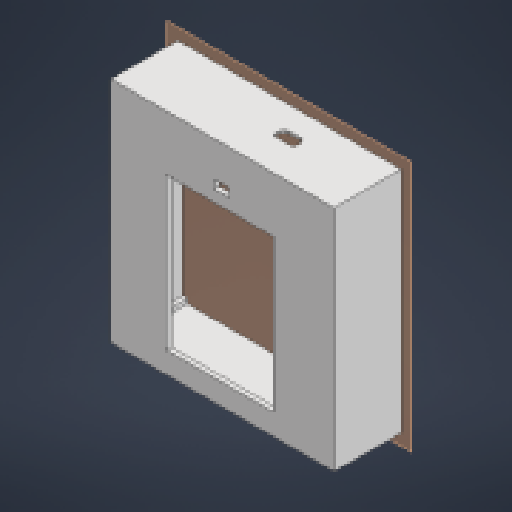
# Autodesk Inventor part: tapadera_pantalla
Saved by Autodesk Inventor 2027.1 (Build 311270010, 270A)
## iProperties
Created: 2026-10-11
Part Number: tapadera_pantalla
Material: Generic
Document SubType Name: Modeling
Designer: MineS
Density: 1 g/cm^3
Appearance: Default
Author: MineS
Autodesk Inventor part; units mm, degrees
ref_plane "YZ Plane" through (0, 0, 0) normal (1, 0, 0) x (0, 1, 0)
ref_plane "XZ Plane" through (0, 0, 0) normal (0, 1, 0) x (-1, 0, 0)
ref_plane "XY Plane" through (0, 0, 0) normal (0, 0, 1) x (1, 0, 0)
ref_plane "Work Plane1" through (0, 0, 0) normal (0, 0, 1) x (1, 0, 0)
sketch "Sketch1" plane through (0, 0, 0) normal (0, 0, 1) x (1, 0, 0)
  line L0 (25.3964, -36.965) -> (25.3964, -37.465) projected
  line L1 (25.3964, -37.465) -> (-26.8636, -37.465) projected
  line L2 (-26.8636, -37.465) -> (-26.8636, -36.965) projected
  line L3 (-35.6316, -36.965) -> (-26.8636, -36.965) projected
  line L4 (-35.6316, 18.933) -> (-35.6316, -36.965) projected
  line L5 (-24.8636, 18.933) -> (-35.6316, 18.933) projected
  line L6 (-24.8636, 18.605) -> (-24.8636, 18.933) projected
  line L7 (-24.8636, 18.605) -> (25.3964, 18.605) projected
  line L8 (25.3964, 18.933) -> (25.3964, 18.605) projected
  line L9 (34.1644, 18.933) -> (25.3964, 18.933) projected
  line L10 (34.1644, -36.965) -> (34.1644, 18.933) projected
  line L11 (25.3964, -36.965) -> (34.1644, -36.965) projected
  line L12 (-45, 46) -> (45, 46) projected
  line L13 (-45, -46) -> (-45, 46) projected
  line L14 (45, -46) -> (-45, -46) projected
  line L15 (45, 46) -> (45, -46) projected
  line L16 (-45, 46) -> (-42.8787, 43.8787)
  circle A0 centre (-42.8787, 43.8787) radius 1.5
  circle A1 centre (42.8787, 43.8787) radius 1.5
  line L17 (45, 46) -> (42.8787, 43.8787)
  line L18 (-45, 46) -> (-45, -46)
  line L19 (-45, 0) -> (45, 0)
  circle A2 centre (-42.8787, -43.8787) radius 1.5
  circle A3 centre (42.8787, -43.8787) radius 1.5
  line L20 (25.3964, -36.965) -> (25.3964, -37.465) projected
  line L21 (25.3964, -37.465) -> (-26.8636, -37.465) projected
  line L22 (-26.8636, -37.465) -> (-26.8636, -36.965) projected
  line L23 (-35.6316, -36.965) -> (-26.8636, -36.965) projected
  line L24 (-35.6316, 18.933) -> (-35.6316, -36.965) projected
  line L25 (-24.8636, 18.933) -> (-35.6316, 18.933) projected
  line L26 (-24.8636, 18.605) -> (-24.8636, 18.933) projected
  line L27 (-24.8636, 18.605) -> (25.3964, 18.605) projected
  line L28 (25.3964, 18.933) -> (25.3964, 18.605) projected
  line L29 (34.1644, 18.933) -> (25.3964, 18.933) projected
  line L30 (34.1644, -36.965) -> (34.1644, 18.933) projected
  line L31 (25.3964, -36.965) -> (34.1644, -36.965) projected
  line L32 (-45, 46) -> (45, 46) projected
  line L33 (-45, -46) -> (-45, 46) projected
  line L34 (45, -46) -> (-45, -46) projected
  line L35 (45, 46) -> (45, -46) projected
  line L36 (-45, 46) -> (-41, 46)
  line L37 (-41, 46) -> (-41, 42)
  line L38 (-41, 42) -> (-45, 42)
  line L39 (-45, 42) -> (-45, 46)
  line L40 (45, 46) -> (41, 46)
  line L41 (41, 46) -> (41, 42)
  line L42 (41, 42) -> (45, 42)
  line L43 (45, 42) -> (45, 46)
  line L44 (-45, -46) -> (-41, -46)
  line L45 (-41, -46) -> (-41, -42)
  line L46 (-41, -42) -> (-45, -42)
  line L47 (-45, -42) -> (-45, -46)
  line L48 (45, -46) -> (41, -46)
  line L49 (41, -46) -> (41, -42)
  line L50 (41, -42) -> (45, -42)
  line L51 (45, -42) -> (45, -46)
  line L52 (-43, 42) -> (-43, -42)
  line L53 (-41, -44) -> (41, -44)
  line L54 (43, -42) -> (43, 42)
  line L55 (32.2664, 44.433) -> (-33.7336, 44.433) projected
  line L56 (-41, 45) -> (41, 45)
  circle A4 centre (-42.8787, -43.8787) radius 1.5 projected
  circle A5 centre (-42.8787, 43.8787) radius 1.5 projected
  circle A6 centre (42.8787, -43.8787) radius 1.5 projected
  circle A7 centre (42.8787, 43.8787) radius 1.5 projected
  circle A8 centre (-42.8787, -43.8787) radius 1.5 projected
  circle A9 centre (-42.8787, 43.8787) radius 1.5 projected
  circle A10 centre (42.8787, -43.8787) radius 1.5 projected
  circle A11 centre (42.8787, 43.8787) radius 1.5 projected
  point P0 (0, 0)
  dimension "d0" = 3
  dimension "d1" = 45
  dimension "d2" = 3
  dimension "d3" = 3
  dimension "d4" = 45
  dimension "d5" = 3
  dimension "d6" = 4
  dimension "d7" = 4
  dimension "d8" = 4
  dimension "d9" = 4
  dimension "d10" = 4
  dimension "d11" = 4
  dimension "d12" = 1
  constraints: 48 end point, 9 equal length, 8 midpoint, 5 perpendicular, 4 centre point, 4 horizontal, 4 point on line, 2 symmetric about line, 1 coincident, 2 other
  measures "d0" distance of L12.start L16.end
  measures "d1" angle of L13 L16
  measures "d2" diameter of A1
  measures "d3" distance of L12.end L17.end
  measures "d4" angle of L17 L15
  measures "d5" diameter of A0
  measures "d6" distance of L36.end L37.end
  measures "d7" distance of L40.end L41.end
  measures "d8" distance of L45.end L46.end
  measures "d9" distance of L44.end L45.end
  measures "d10" distance of L49.end L50.end
  measures "d11" distance of L48.end L49.end
  measures "d12" distance of L40.end L56.end
ref_plane "Work Plane2" through (0, 0, 0) normal (0, 0, 1) x (1, 0, 0)
extrude "Extrusion1" add sketch "Sketch1" along normal blind 25 contours L54 L42 L15 L19 | L19 L15 L50 L54 | L52 L46 L13 L19 | L19 L13 L38 L52 | L50 L15 L14 L49 | L42 L41 L12 L15 | L38 L13 L12 L37 | L46 L45 L14 L13 | L49 L14 L45 L53 | L56 L37 L12 L41
sketch "Sketch3" plane through (0, 0, 25) normal (0, 0, 1) x (1, 0, 0)
  line L0 (20.3301, -36.9587) -> (-22.3899, -36.9587) projected
  line L1 (-22.3899, -36.9587) -> (-22.3899, 23.3013) projected
  line L2 (20.3301, -36.9587) -> (20.3301, 23.3013) projected
  line L3 (20.3301, 23.3013) -> (-22.3899, 23.3013) projected
  line L4 (-45, 46) -> (-45, -46) projected
  line L5 (-45, -46) -> (45, -46) projected
  line L6 (45, -46) -> (45, 46) projected
  line L7 (45, 46) -> (-45, 46) projected
  circle A0 centre (42.8787, 43.8787) radius 1.5 projected
  circle A1 centre (-42.8787, 43.8787) radius 1.5 projected
  circle A2 centre (42.8787, -43.8787) radius 1.5 projected
  circle A3 centre (-42.8787, -43.8787) radius 1.5 projected
  line L8 (-41, 45) -> (41, 45) projected
  line L9 (41, 45) -> (41, 42) projected
  line L10 (41, 42) -> (43, 42) projected
  line L11 (43, 42) -> (43, -42) projected
  line L12 (43, -42) -> (41, -42) projected
  line L13 (41, -42) -> (41, -44) projected
  line L14 (41, -44) -> (-41, -44) projected
  line L15 (-41, -44) -> (-41, -42) projected
  line L16 (-41, -42) -> (-43, -42) projected
  line L17 (-43, -42) -> (-43, 42) projected
  line L18 (-43, 42) -> (-41, 42) projected
  line L19 (-41, 42) -> (-41, 45) projected
  line L20 (45, 46) -> (-45, 46)
  line L21 (-45, 46) -> (-45, -46)
  line L22 (-45, -46) -> (45, -46)
  line L23 (45, -46) -> (45, 46)
  line L24 (20.7301, 23.7013) -> (20.7301, -37.3587)
  line L25 (20.7301, -37.3587) -> (-22.7899, -37.3587)
  line L26 (-22.7899, -37.3587) -> (-22.7899, 23.7013)
  line L27 (-22.7899, 23.7013) -> (20.7301, 23.7013)
  point P0 (0, 0)
  dimension "d15" = 0.4
  constraints: 16 end point, 2 parallel, 1 horizontal, 1 perpendicular, 3 other
  measures "d15" distance between parallel lines of L0 L25
extrude "Extrusion2" add sketch "Sketch3" along normal blind 2 contours L7 L6 L5 L4 | A0 | A1 | A2 | A3 | L8 L9 L10 L11 L12 L13 L14 L15 L16 L17 L18 L19
sketch "Sketch4" plane through (0, 0, 27) normal (0, 0, 1) x (1, 0, 0)
  line L0 (-3.2699, 28.4713) -> (2.7301, 28.4713) projected
  line L1 (2.7301, 31.8713) -> (-3.2699, 31.8713) projected
  line L2 (-3.2699, 28.5713) -> (-3.2699, 29.7213) projected
  line L3 (-3.2699, 31.8713) -> (-3.2699, 30.7213) projected
  line L4 (2.7301, 31.8713) -> (2.7301, 30.7343) projected
  line L5 (2.7301, 28.5713) -> (2.7301, 29.7343) projected
  line L6 (-3.2699, 31.8713) -> (2.7301, 31.8713)
  line L7 (2.7301, 31.8713) -> (2.7301, 28.4713)
  line L8 (2.7301, 28.4713) -> (-3.2699, 28.4713)
  line L9 (-3.2699, 28.4713) -> (-3.2699, 31.8713)
  point P0 (0, 0)
  constraints: 8 end point, 2 parallel, 1 horizontal, 1 perpendicular
extrude "Extrusion3" cut sketch "Sketch4" against normal blind 2
sketch "Sketch5" plane through (-45, 46, 0) normal (0, 1, 0) x (1, 0, 0)
  line L0 (53.9137, -9.67) -> (56.3235, -9.67) projected
  line L1 (56.3335, -9.67) -> (58.7433, -9.67) projected
  line L2 (59.3155, -9.9667) -> (60.0507, -11.0095) projected
  line L3 (60.1785, -11.4129) -> (60.1785, -12.87) projected
  line L4 (59.4785, -13.57) -> (53.1785, -13.57) projected
  line L5 (52.4785, -12.87) -> (52.4785, -11.4129) projected
  line L6 (52.6064, -11.0095) -> (53.3416, -9.9667) projected
  line L7 (53.3416, -9.9667) -> (52.6064, -11.0095)
  line L8 (52.4785, -11.4129) -> (52.4785, -12.87)
  line L9 (53.1785, -13.57) -> (59.4785, -13.57)
  line L10 (60.1785, -12.87) -> (60.1785, -11.4129)
  arc A0 (53.9137, -9.67) -> (53.3416, -9.9667) centre (53.9137, -10.37) ccw projected
  arc A1 (59.3155, -9.9667) -> (58.7433, -9.67) centre (58.7433, -10.37) ccw projected
  arc A2 (59.4785, -13.57) -> (60.1785, -12.87) centre (59.4785, -12.87) ccw projected
  arc A3 (60.1785, -11.4129) -> (60.0507, -11.0095) centre (59.4785, -11.4129) ccw projected
  arc A4 (52.4785, -12.87) -> (53.1785, -13.57) centre (53.1785, -12.87) ccw projected
  arc A5 (52.6064, -11.0095) -> (52.4785, -11.4129) centre (53.1785, -11.4129) ccw projected
  line L11 (56.3335, -9.27) -> (58.7433, -9.27)
  arc A6 (59.6424, -9.7362) -> (58.7433, -9.27) centre (58.7433, -10.37) ccw
  line L12 (59.6424, -9.7362) -> (60.3776, -10.779)
  arc A7 (60.5785, -11.4129) -> (60.3776, -10.779) centre (59.4785, -11.4129) ccw
  line L13 (60.5785, -11.4129) -> (60.5785, -12.87)
  arc A8 (59.4785, -13.97) -> (60.5785, -12.87) centre (59.4785, -12.87) ccw
  line L14 (59.4785, -13.97) -> (53.1785, -13.97)
  arc A9 (52.0785, -12.87) -> (53.1785, -13.97) centre (53.1785, -12.87) ccw
  line L15 (52.0785, -12.87) -> (52.0785, -11.4129)
  arc A10 (52.2795, -10.779) -> (52.0785, -11.4129) centre (53.1785, -11.4129) ccw
  line L16 (52.2795, -10.779) -> (53.0147, -9.7362)
  arc A11 (53.9137, -9.27) -> (53.0147, -9.7362) centre (53.9137, -10.37) ccw
  line L17 (53.9137, -9.27) -> (56.3235, -9.27)
  line L18 (53.1785, -13.97) -> (59.4785, -13.97)
  line L19 (60.5785, -11.4129) -> (60.5785, -12.87)
  line L20 (58.7433, -9.27) -> (53.9137, -9.27)
  line L21 (53.0147, -9.7362) -> (52.2795, -10.779)
  line L22 (52.0785, -11.4129) -> (52.0785, -12.87)
  arc A12 (53.9137, -9.27) -> (53.0147, -9.7362) centre (53.9137, -10.37) ccw
  arc A13 (52.2795, -10.779) -> (52.0785, -11.4129) centre (53.1785, -11.4129) ccw
  arc A14 (52.0785, -12.87) -> (53.1785, -13.97) centre (53.1785, -12.87) ccw
  arc A15 (59.4785, -13.97) -> (60.5785, -12.87) centre (59.4785, -12.87) ccw
  arc A16 (60.5785, -11.4129) -> (60.3776, -10.779) centre (59.4785, -11.4129) ccw
  arc A17 (59.6424, -9.7362) -> (58.7433, -9.27) centre (58.7433, -10.37) ccw
  point P0 (45, 0)
  dimension "d20" = 0.4
  constraints: 32 end point, 27 point on circle, 12 centre point, 7 tangent, 6 collinear, 2 perpendicular, 1 concentric, 12 other
  measures "d20" distance between parallel lines of L11 L1
extrude "Extrusion4" cut sketch "Sketch5" against normal blind 4
sketch "Sketch6" plane through (-45, -46, 0) normal (-1, 0, 0) x (0, 0, 1)
  circle A0 centre (19, 84) radius 1.45
  circle A1 centre (19, 8) radius 1.45
  line L0 (0, 92) -> (0, 0) projected
  line L1 (0, 0) -> (27, 0) projected
  line L2 (27, 92) -> (27, 0) projected
  line L3 (0, 92) -> (27, 92) projected
  point P0 (0, 46)
  dimension "d23" = 2.9
  dimension "d24" = 2.9
  dimension "d25" = 8
  dimension "d26" = 8
  dimension "d27" = 8
  dimension "d28" = 8
  constraints: 2 centre point
  measures "d23" diameter of A1
  measures "d24" diameter of A0
  measures "d25" distance from line of L3 A0.centre
  measures "d26" distance from line of L2 A0.centre
  measures "d27" distance from line of L1 A1.centre
  measures "d28" distance from line of L2 A1.centre
extrude "Extrusion5" cut sketch "Sketch6" against normal blind 4 contours A0 | A1
mirror "Mirror1" about plane through (0, 0, 0) normal (1, 0, 0) of "Extrusion5"
body "Solid1"
